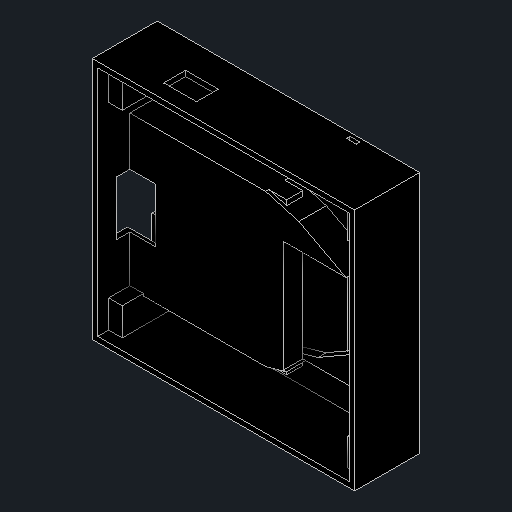
# Autodesk Inventor part: Enclosure Base
Saved by Autodesk Inventor 2027.2 (Build 312334000, 334)
## iProperties
Created: 2026-11-11
Part Number: Enclosure Base
Material: Generic
Description: Enclosure base: rear-entry pouch tunnel (tall at the entrance, 3 mm under the sensors), LFA strip groove, module opening
Document SubType Name: Modeling
Designer: isaac
Density: 1 g/cm^3
Appearance: Black
Author: isaac
Autodesk Inventor part; units mm, degrees
ref_plane "Work Plane1" through (0, 0, -19.9) normal (0, 0, 1) x (1, 0, 0)
sketch "Sketch1" plane through (0, 0, -19.9) normal (0, 0, 1) x (1, 0, 0)
  line L0 (-3.5, -8) -> (93, -8)
  line L1 (93, -8) -> (93, 81.5)
  line L2 (93, 81.5) -> (-3.5, 81.5)
  line L3 (-3.5, 81.5) -> (-3.5, -8)
  constraints: 8 end point, 2 parallel, 1 horizontal, 1 perpendicular
extrude "Shell" add sketch "Sketch1" along normal blind 23.9
ref_plane "Work Plane2" through (0, 0, -17.9) normal (0, 0, 1) x (1, 0, 0)
sketch "Sketch2" plane through (0, 0, -17.9) normal (0, 0, 1) x (1, 0, 0)
  line L0 (-1.5, -6) -> (91, -6)
  line L1 (91, -6) -> (91, 79.5)
  line L2 (91, 79.5) -> (-1.5, 79.5)
  line L3 (-1.5, 79.5) -> (-1.5, -6)
  constraints: 8 end point, 2 parallel, 1 horizontal, 1 perpendicular
extrude "Pocket" cut sketch "Sketch2" along normal blind 21.9
ref_plane "Work Plane3" through (0, 0, -17.9) normal (0, 0, 1) x (1, 0, 0)
sketch "Sketch3" plane through (0, 0, -17.9) normal (0, 0, 1) x (1, 0, 0)
  line L0 (55, 5.63) -> (85.8, 5.63)
  line L1 (85.8, 5.63) -> (85.8, 46.59)
  line L2 (85.8, 46.59) -> (55, 46.59)
  line L3 (55, 46.59) -> (55, 5.63)
  constraints: 8 end point, 2 parallel, 1 horizontal, 1 perpendicular
extrude "Module pedestal" add sketch "Sketch3" along normal blind 3
ref_plane "Work Plane4" through (0, 0, -17.9) normal (0, 0, 1) x (1, 0, 0)
sketch "Sketch4" plane through (0, 0, -17.9) normal (0, 0, 1) x (1, 0, 0)
  line L0 (85.05, 19.8165) -> (60.66, 6.9265)
  line L1 (60.66, 6.9265) -> (48.45, 3.4465)
  line L2 (48.45, 3.4465) -> (0.65, 3.4465)
  line L3 (0.65, 3.4465) -> (-3.5, 3.4465)
  line L4 (-3.5, 3.4465) -> (-3.5, 59.2465)
  line L5 (-3.5, 59.2465) -> (0.65, 59.2465)
  line L6 (0.65, 59.2465) -> (48.45, 59.2465)
  line L7 (48.45, 59.2465) -> (60.66, 55.7665)
  line L8 (60.66, 55.7665) -> (85.05, 42.8765)
  line L9 (85.05, 42.8765) -> (85.05, 19.8165)
  constraints: 20 end point
extrude "Tunnel" add sketch "Sketch4" along normal blind 10.1
ref_plane "Work Plane5" through (0, 0, -17.9) normal (0, 0, 1) x (1, 0, 0)
sketch "Sketch5" plane through (0, 0, -17.9) normal (0, 0, 1) x (1, 0, 0)
  line L0 (83.05, 21.8165) -> (60.66, 8.9265)
  line L1 (60.66, 8.9265) -> (48.45, 5.4465)
  line L2 (48.45, 5.4465) -> (0.65, 5.4465)
  line L3 (0.65, 5.4465) -> (-3.75, 5.4465)
  line L4 (-3.75, 5.4465) -> (-5.5, 5.4465)
  line L5 (-5.5, 5.4465) -> (-5.5, 57.2465)
  line L6 (-5.5, 57.2465) -> (-3.75, 57.2465)
  line L7 (-3.75, 57.2465) -> (0.65, 57.2465)
  line L8 (0.65, 57.2465) -> (48.45, 57.2465)
  line L9 (48.45, 57.2465) -> (60.66, 53.7665)
  line L10 (60.66, 53.7665) -> (83.05, 40.8765)
  line L11 (83.05, 40.8765) -> (83.05, 21.8165)
  constraints: 24 end point
extrude "Pouch slot" cut sketch "Sketch5" along normal blind 8.9
ref_plane "Work Plane6" through (0, 0, -14.9) normal (0, 0, 1) x (1, 0, 0)
sketch "Sketch6" plane through (0, 0, -14.9) normal (0, 0, 1) x (1, 0, 0)
  line L0 (44, 3.4465) -> (55, 3.4465)
  line L1 (55, 3.4465) -> (55, 59.2465)
  line L2 (55, 59.2465) -> (44, 59.2465)
  line L3 (44, 59.2465) -> (44, 3.4465)
  constraints: 8 end point, 2 parallel, 1 horizontal, 1 perpendicular
extrude "Low ceiling" add sketch "Sketch6" along normal blind 5.9
ref_plane "Work Plane7" through (0, 0, -14.9) normal (0, 0, 1) x (1, 0, 0)
sketch "Sketch7" plane through (0, 0, -14.9) normal (0, 0, 1) x (1, 0, 0)
  line L0 (55, 5.63) -> (85.8, 5.63)
  line L1 (85.8, 5.63) -> (85.8, 46.59)
  line L2 (85.8, 46.59) -> (55, 46.59)
  line L3 (55, 46.59) -> (55, 5.63)
  constraints: 8 end point, 2 parallel, 1 horizontal, 1 perpendicular
extrude "Module opening" cut sketch "Sketch7" along normal blind 18.9
ref_plane "Work Plane8" through (0, 0, -18.6) normal (0, 0, 1) x (1, 0, 0)
sketch "Sketch8" plane through (0, 0, -18.6) normal (0, 0, 1) x (1, 0, 0)
  line L0 (68.6125, 10.43) -> (72.1875, 10.43)
  line L1 (72.1875, 10.43) -> (72.1875, 82.5)
  line L2 (72.1875, 82.5) -> (68.6125, 82.5)
  line L3 (68.6125, 82.5) -> (68.6125, 10.43)
  constraints: 8 end point, 2 parallel, 1 horizontal, 1 perpendicular
extrude "Strip groove" cut sketch "Sketch8" along normal blind 0.7
ref_plane "Work Plane9" through (0, 0, -17.9) normal (0, 0, 1) x (1, 0, 0)
sketch "Sketch9" plane through (0, 0, -17.9) normal (0, 0, 1) x (1, 0, 0)
  line L0 (68.6125, 79.4) -> (72.1875, 79.4)
  line L1 (72.1875, 79.4) -> (72.1875, 82.5)
  line L2 (72.1875, 82.5) -> (68.6125, 82.5)
  line L3 (68.6125, 82.5) -> (68.6125, 79.4)
  constraints: 8 end point, 2 parallel, 1 horizontal, 1 perpendicular
extrude "Strip slot" cut sketch "Sketch9" along normal blind 0.6
ref_plane "Work Plane10" through (0, 0, -17.9) normal (0, 0, 1) x (1, 0, 0)
sketch "Sketch10" plane through (0, 0, -17.9) normal (0, 0, 1) x (1, 0, 0)
  line L0 (-1.5, -6) -> (3.5, -6)
  line L1 (3.5, -6) -> (3.5, 4.25)
  line L2 (3.5, 4.25) -> (-1.5, 4.25)
  line L3 (-1.5, 4.25) -> (-1.5, -6)
  line L4 (86.5, -6) -> (91, -6)
  line L5 (91, -6) -> (91, 4.25)
  line L6 (91, 4.25) -> (86.5, 4.25)
  line L7 (86.5, 4.25) -> (86.5, -6)
  line L8 (-1.5, 66.5) -> (3.5, 66.5)
  line L9 (3.5, 66.5) -> (3.5, 79.5)
  line L10 (3.5, 79.5) -> (-1.5, 79.5)
  line L11 (-1.5, 79.5) -> (-1.5, 66.5)
  line L12 (86.5, 66.5) -> (91, 66.5)
  line L13 (91, 66.5) -> (91, 79.5)
  line L14 (91, 79.5) -> (86.5, 79.5)
  line L15 (86.5, 79.5) -> (86.5, 66.5)
  constraints: 32 end point, 8 parallel, 4 horizontal, 4 perpendicular
extrude "Board posts" add sketch "Sketch10" along normal blind 17.9
ref_plane "Work Plane11" through (0, 0, -9.4) normal (0, 0, 1) x (1, 0, 0)
sketch "Sketch11" plane through (0, 0, -9.4) normal (0, 0, 1) x (1, 0, 0)
  line L0 (17.41, 79.4) -> (29.41, 79.4)
  line L1 (29.41, 79.4) -> (29.41, 82)
  line L2 (29.41, 82) -> (17.41, 82)
  line L3 (17.41, 82) -> (17.41, 79.4)
  constraints: 8 end point, 2 parallel, 1 horizontal, 1 perpendicular
extrude "USB opening" cut sketch "Sketch11" along normal blind 8
ref_plane "Work Plane12" through (0, 0, -20.4) normal (0, 0, 1) x (1, 0, 0)
sketch "Sketch12" plane through (0, 0, -20.4) normal (0, 0, 1) x (1, 0, 0)
  line L0 (-4.5, 21.3465) -> (8, 21.3465)
  line L1 (8, 21.3465) -> (8, 41.3465)
  line L2 (8, 41.3465) -> (-4.5, 41.3465)
  line L3 (-4.5, 41.3465) -> (-4.5, 21.3465)
  constraints: 8 end point, 2 parallel, 1 horizontal, 1 perpendicular
extrude "Finger notch below" cut sketch "Sketch12" along normal blind 2.5
ref_plane "Work Plane13" through (0, 0, -9) normal (0, 0, 1) x (1, 0, 0)
sketch "Sketch13" plane through (0, 0, -9) normal (0, 0, 1) x (1, 0, 0)
  line L0 (-4.5, 21.3465) -> (8, 21.3465)
  line L1 (8, 21.3465) -> (8, 41.3465)
  line L2 (8, 41.3465) -> (-4.5, 41.3465)
  line L3 (-4.5, 41.3465) -> (-4.5, 21.3465)
  constraints: 8 end point, 2 parallel, 1 horizontal, 1 perpendicular
extrude "Finger notch above" cut sketch "Sketch13" along normal blind 6
body "Solid1"
